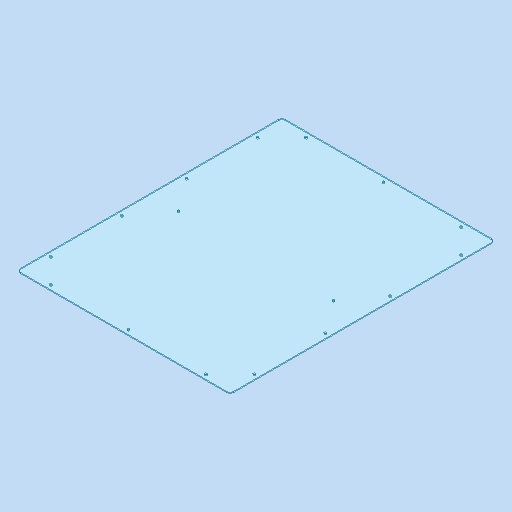
# Autodesk Inventor part: MM0937AN200_G03_147
Saved by Autodesk Inventor 2023.3 (Build 273359000, 359)
## iProperties
Part Number: MM0937AN200_G03_147
Material: Kst - PC (Eslon, klar)
Description: =<RBPARTNOTITLE2>
Document SubType Name: Modeling
Designer: Benutzer
Mass: 1945.79 g
Surface Area: 10908.8 cm^2
Volume: 1621.5 cm^3
Density: 1.2 g/cm^3
Appearance: Klar AnP
Vendor: Koenig
RBDOCUMENTTYPE: DRF
RBDOCUMENTVERSION: 00
RBDRAWINGMAINSCALE: 1:1
RBDRAWINGMISSINGSPEC: --
RBDRAWINGVOLUME: --
RBGBEDGESIN1: +0,5
RBGBEDGESIN2: +0,2
RBGBEDGESOUT1: -0,3
RBGBEDGESOUT2: -0,1
RBMATERIAL: =<Material>
RBMATMEETS: --
RBMATNO: =<Part Number>
RBPARTMADEOF: 3 x 820 x 660 (FM)
RBPARTNO: SIEHE MNR
RBPARTNOTITLE1: manufactured part
RBPARTNOTITLE2: Anfertigungsteil
RBPARTSAFETYINDICATOR: --
RBSURFACE: --
RBSURFACE2: --
RBZEDGESNORM: ISO13715:2002-06
RBZGENDIMCLASS: m
RBZGENDIMNORM: ISO 2768-1:1989-11
RBZGENGEOCLASS: H
RBZGENGEONORM: ISO 2768-2:1989-11
RBZSURFACENORM: ISO13D2:2002-02
RBZTOLERANCENORM: ISO 14405-1:2010-12
AnP_Material: =<Material>
AnP_TemplVers: 20190222
AnP_Kategorie: 1
MaxAbmaße: 3 x 820 x 660 (FM)
Author: Benutzer
Keywords: =<RBPARTMADEOF>
Comments: =<RBSURFACE2>
Revision Number: 01
Autodesk Inventor part; units mm, degrees
ref_plane "YZ Plane" through (0, 0, 0) normal (1, 0, 0) x (0, 1, 0)
ref_plane "XZ Plane" through (0, 0, 0) normal (0, 1, 0) x (-1, 0, 0)
ref_plane "XY Plane" through (0, 0, 0) normal (0, 0, 1) x (1, 0, 0)
sketch "Skizze1" plane through (0, 0, 0) normal (0, 0, 1) x (1, 0, 0)
  line L0 (0, 0) -> (660, 0)
  line L1 (660, 0) -> (660, 820)
  line L2 (660, 820) -> (0, 820)
  line L3 (0, 820) -> (0, 0)
  dimension "d0" = 660
  dimension "d1" = 820
  constraints: 8 end point, 2 parallel, 1 horizontal, 1 perpendicular
  measures "d0" distance of L2.end L1.end
  measures "d1" distance of L1.end L0.end
extrude "Extrusion1" add sketch "Skizze1" along normal blind 3
fillet "Rundung1" radius 10 4 edges at (660, 0, 1.5) (0, 0, 1.5) (0, 820, 1.5) (660, 820, 1.5)
sketch "Skizze2" plane through (0, 0, 3) normal (0, 0, 1) x (1, 0, 0)
  line L0 (650, 820) -> (10, 820) projected
  line L1 (0, 810) -> (0, 10) projected
  line L2 (660, 10) -> (660, 810) projected
  line L3 (10, 0) -> (650, 0) projected
  point P0 (0, 0)
  point P1 (90, 805)
  point P2 (330, 805)
  point P3 (570, 805)
  point P4 (645, 730)
  point P5 (645, 510)
  point P6 (645, 310)
  point P7 (645, 90)
  point P8 (570, 15)
  point P9 (330, 15)
  point P10 (90, 15)
  point P11 (15, 90)
  point P12 (15, 310)
  point P13 (15, 510)
  point P14 (15, 730)
  dimension "d5" = 15
  dimension "d6" = 15
  dimension "d7" = 15
  dimension "d8" = 15
  dimension "d12" = 660
  dimension "d13" = 90
  dimension "d14" = 220
  dimension "d15" = 200
  dimension "d16" = 220
  dimension "d17" = 820
  dimension "d18" = 90
  dimension "d35" = 90
  dimension "d36" = 480
  dimension "d37" = 240
  constraints: 9 vertical alignment, 8 horizontal alignment
  measures "d5" distance from line of point (90, 805) L0
  measures "d6" distance from line of point (15, 730) L1
  measures "d7" distance from line of point (645, 730) L2
  measures "d8" distance from line of L3 point (90, 15)
  measures "d12" distance between parallel lines of L2 L1
  measures "d13" distance from line of point (90, 15) L1
  measures "d14" distance of point (15, 310) point (15, 90)
  measures "d15" distance of point (15, 510) point (15, 310)
  measures "d16" distance of point (15, 730) point (15, 510)
  measures "d17" distance between parallel lines of L3 L0
  measures "d18" distance from line of point (15, 730) L0
  measures "d35" distance from line of point (570, 15) L2
  measures "d36" distance of point (570, 15) point (90, 15)
  measures "d37" distance of point (330, 15) point (90, 15)
hole "Bohrung1" at (90, 805, 3) at (330, 805, 3) at (570, 805, 3) at (645, 730, 3) at (645, 510, 3) at (645, 310, 3) at (645, 90, 3) at (570, 15, 3) at (330, 15, 3) at (90, 15, 3) at (15, 90, 3) at (15, 310, 3) at (15, 510, 3) at (15, 730, 3) direction (0, 0, -1) diameter 7 depth 8 tip angle 118
sketch "Skizze3" plane through (0, 0, 3) normal (0, 0, 1) x (1, 0, 0)
  circle A0 centre (15, 510) radius 3.5 projected
  circle A1 centre (330, 15) radius 3.5 projected
  circle A2 centre (645, 510) radius 3.5 projected
  circle A3 centre (330, 805) radius 3.5 projected
  circle A4 centre (90, 805) radius 3.5 projected
  circle A5 centre (570, 805) radius 3.5 projected
  circle A6 centre (645, 730) radius 3.5 projected
  circle A7 centre (645, 310) radius 3.5 projected
  circle A8 centre (570, 15) radius 3.5 projected
  circle A9 centre (90, 15) radius 3.5 projected
  circle A10 centre (15, 310) radius 3.5 projected
  circle A11 centre (15, 730) radius 3.5 projected
  arc A12 (660, 810) -> (650, 820) centre (650, 810) ccw projected
  line L0 (650, 820) -> (10, 820) projected
  arc A13 (10, 820) -> (0, 810) centre (10, 810) ccw projected
  line L1 (0, 810) -> (0, 10) projected
  arc A14 (0, 10) -> (10, 0) centre (10, 10) ccw projected
  line L2 (10, 0) -> (650, 0) projected
  arc A15 (650, 0) -> (660, 10) centre (650, 10) ccw projected
  line L3 (660, 10) -> (660, 810) projected
  point P0 (0, 0)
  point P1 (90, 410)
  point P2 (570, 410)
  dimension "d26" = 395
  dimension "d34" = 480
  constraints: 1 horizontal alignment, 1 vertical alignment
  measures "d26" distance of point (90, 410) A4.centre
  measures "d34" distance of point (570, 410) point (90, 410)
hole "Bohrung2" at (90, 410, 3) at (570, 410, 3) direction (0, 0, -1) diameter 7 depth 8 tip angle 118
equation "\"d37\" = 0.5 * d36"
